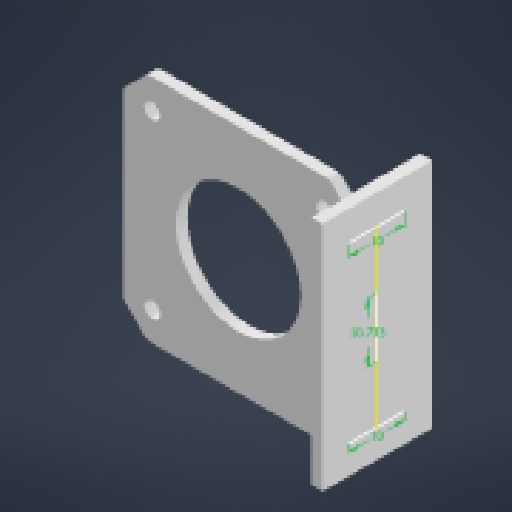
# Autodesk Inventor part: Gia_truc_z
Saved by Autodesk Inventor 2026.2 (Build 302298000, 298)
## iProperties
Created: 2026-07-05
Part Number: Gia_truc_z
Material: Generic
Document SubType Name: Modeling
Designer: thita
Density: 1 g/cm^3
Appearance: Default
Author: thita
Autodesk Inventor part; units mm, degrees
ref_plane "YZ Plane" through (0, 0, 0) normal (1, 0, 0) x (0, 1, 0)
ref_plane "XZ Plane" through (0, 0, 0) normal (0, 1, 0) x (-1, 0, 0)
sketch "Sketch1" plane through (0, 0, 0) normal (0, 0, 1) x (1, 0, 0)
  line L0 (20.8, -15.6716) -> (20.8, 15.6716)
  arc A0 (20.8, 15.6716) -> (20.2728, 16.9444) centre (19, 15.6716) ccw
  line L1 (20.2728, 16.9444) -> (16.9444, 20.2728)
  arc A1 (16.9444, 20.2728) -> (15.6716, 20.8) centre (15.6716, 19) ccw
  line L2 (15.6716, 20.8) -> (-15.6716, 20.8)
  arc A2 (-15.6716, 20.8) -> (-16.9444, 20.2728) centre (-15.6716, 19) ccw
  line L3 (-16.9444, 20.2728) -> (-20.2728, 16.9444)
  arc A3 (-20.2728, 16.9444) -> (-20.8, 15.6716) centre (-19, 15.6716) ccw
  line L4 (-20.8, 15.6716) -> (-20.8, -15.6716)
  arc A4 (-20.8, -15.6716) -> (-20.2728, -16.9444) centre (-19, -15.6716) ccw
  line L5 (-20.2728, -16.9444) -> (-16.9444, -20.2728)
  arc A5 (-16.9444, -20.2728) -> (-15.6716, -20.8) centre (-15.6716, -19) ccw
  line L6 (-15.6716, -20.8) -> (15.6716, -20.8)
  arc A6 (15.6716, -20.8) -> (16.9444, -20.2728) centre (15.6716, -19) ccw
  line L7 (16.9444, -20.2728) -> (20.2728, -16.9444)
  arc A7 (20.2728, -16.9444) -> (20.8, -15.6716) centre (19, -15.6716) ccw
  circle A8 centre (0, 0) radius 11.2
  circle A9 centre (15.5, 15.5) radius 1.45
  circle A10 centre (-15.5, 15.5) radius 1.45
  circle A11 centre (-15.5, -15.5) radius 1.45
  circle A12 centre (15.5, -15.5) radius 1.45
  constraints: 16 end point, 16 point on circle, 13 centre point
extrude "Extrusion1" add sketch "Sketch1" along normal blind 2
sketch "Sketch3" plane through (-15.6716, -20.8, 0) normal (0, -1, 0) x (1, 0, 0)
  line L0 (36.6716, 9.8) -> (36.6716, 2.2) projected
  line L1 (36.6716, 9.8) -> (38.6716, 9.8)
  line L2 (38.6716, 9.8) -> (38.6716, 0)
  line L3 (36.4716, 0) -> (36.4716, 2) projected
  line L4 (38.6716, 0) -> (36.4716, 0)
  arc A0 (36.4716, 2) -> (36.6716, 2.2) centre (36.4716, 2.2) ccw projected
  line L5 (36.6716, 9.8) -> (36.6716, 2.2) projected
  point P0 (15.6716, 0)
  dimension "d8" = 2
  constraints: 6 end point, 2 perpendicular, 1 horizontal
  measures "d8" distance of L0.start L1.end
ref_plane "Work Plane1" through (-15.6716, 21, 2.2) normal (0, 1, 0) x (0, 0, 1)
extrude "Extrusion3" add sketch "Sketch3" against normal up to surface (41.8 mm away)
sketch "Sketch4" plane through (0, 0, 0) normal (0, 0, -1) x (-1, 0, 0)
  line L0 (-23, -20.8) -> (-23, 21) projected
  line L1 (-20.8, 21) -> (-23, 21) projected
  line L2 (-20.8, -20.8) -> (-23, -20.8) projected
  line L3 (-20.8, 21) -> (-20.8, -20.8)
  point P0 (0, 0)
  constraints: 2 end point, 1 vertical
extrude "Extrusion4" add sketch "Sketch4" along normal blind 10
sketch "Sketch5" plane through (23, -20.8, 9.8) normal (1, 0, 0) x (0, 0, -1)
  line L0 (9.8, 26.1665) -> (9.8, 15.4335)
  line L1 (9.8, 36.4716) -> (9.8, 5.1284) projected
  line L2 (14.8, 5.1284) -> (4.8, 5.1284)
  line L3 (14.8, 36.4716) -> (4.8, 36.4716)
  point P0 (9.8, 20.8)
  dimension "d13" = 10.733
  dimension "d14" = 10
  dimension "d15" = 10
  constraints: 6 end point, 3 midpoint, 1 horizontal, 1 parallel, 1 point on line
  measures "d13" distance of L0.start L0.end
  measures "d14" distance of L2.start L2.end
  measures "d15" distance of L3.start L3.end
body "Solid1"
